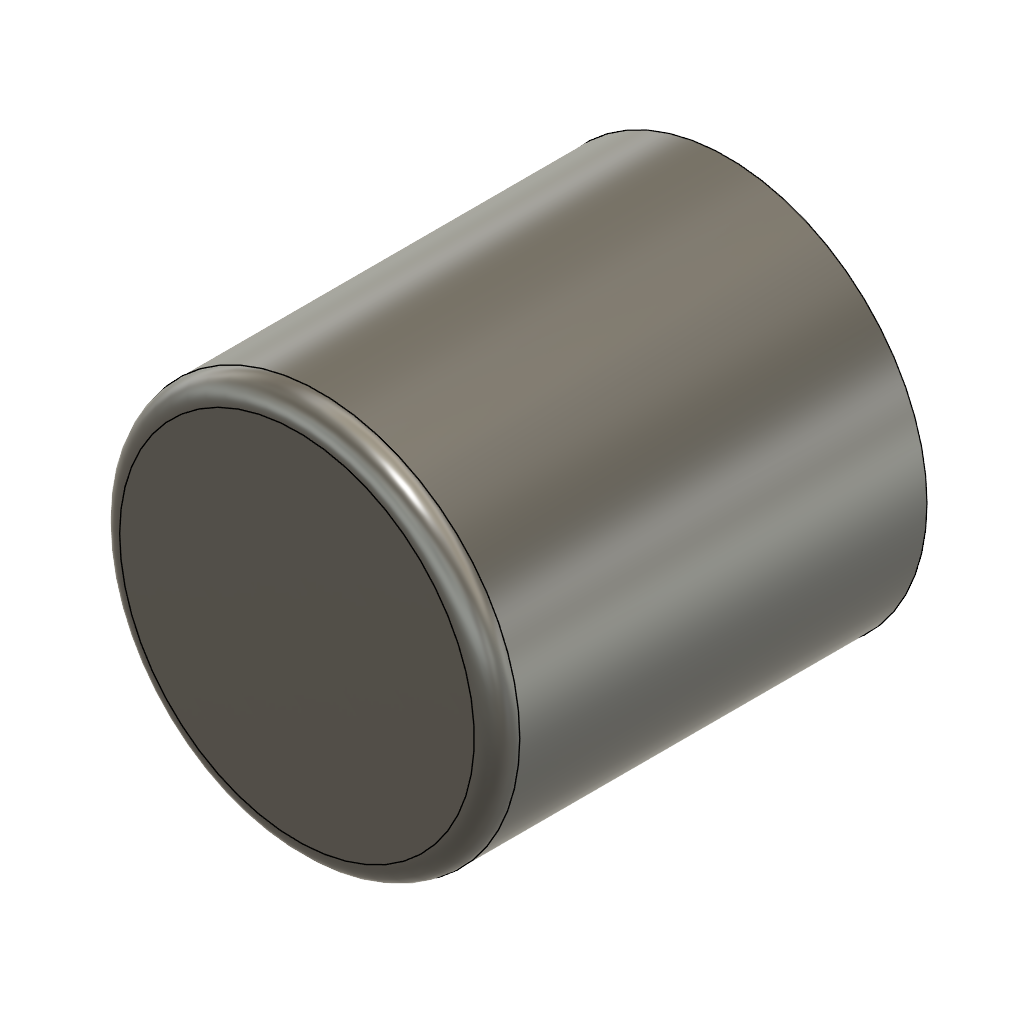
Native (Autodesk Fusion 360 design; units mm, degrees)
part number: 2026-11-25-23-00-45-136
Autodesk Fusion 360 part; units mm, degrees
sketch "Disc sketch" plane through (0, 0, 0) normal (0, 0, 1) x (1, 0, 0)
  circle A0 centre (0, 0) radius 16.7
extrude "Disc extrude" add sketch "Disc sketch" along normal blind 35.9
fillet "Rim round" radius 1.9 1 edges at (-15.5699, -6.039, 35.9)
